Autodesk Fusion 360 part; units mm, degrees
(part 3 of 3)
ref_plane "WorkPlane287" through (0, 27.62, 0) normal (0, 1, 0) x (0, 0, 1)
sketch "Clip release relocated clear of switch" plane through (0, 27.62, 0) normal (0, 1, 0) x (1, 0, 0)
  line L0 (40, -30.3) -> (46, -30.3)
  line L1 (46, -30.3) -> (46, -31.65)
  line L2 (46, -31.65) -> (40, -31.65)
  line L3 (40, -31.65) -> (40, -30.3)
extrude "Clip release relocated clear of switch (1)" cut sketch "Clip release relocated clear of switch" against normal blind 2.1 bodies 1
ref_plane "WorkPlane288" through (0, 0, -4.08) normal (0, 0, 1) x (1, 0, 0)
sketch "Battery landing pad defines assembly bottom datum" plane through (0, 0, -4.08) normal (0, 0, 1) x (1, 0, 0)
  line L0 (-19, -26) -> (-15, -26)
  line L1 (-15, -26) -> (-15, -20)
  line L2 (-15, -20) -> (-19, -20)
  line L3 (-19, -20) -> (-19, -26)
extrude "Battery landing pad defines assembly bottom datum (1)" add sketch "Battery landing pad defines assembly bottom datum" along normal blind 0.95 bodies 1
ref_plane "WorkPlane289" through (0, 0, -4.08) normal (0, 0, 1) x (1, 0, 0)
sketch "Battery landing pad defines assembly bottom datum (1)" plane through (0, 0, -4.08) normal (0, 0, 1) x (1, 0, 0)
  line L0 (-19, 10) -> (-15, 10)
  line L1 (-15, 10) -> (-15, 16)
  line L2 (-15, 16) -> (-19, 16)
  line L3 (-19, 16) -> (-19, 10)
extrude "Battery landing pad defines assembly bottom datum (2)" add sketch "Battery landing pad defines assembly bottom datum (1)" along normal blind 0.95 bodies 1
ref_plane "WorkPlane290" through (0, 0, -4.08) normal (0, 0, 1) x (1, 0, 0)
sketch "Battery landing pad defines assembly bottom datum (2)" plane through (0, 0, -4.08) normal (0, 0, 1) x (1, 0, 0)
  line L0 (9, -26) -> (13, -26)
  line L1 (13, -26) -> (13, -20)
  line L2 (13, -20) -> (9, -20)
  line L3 (9, -20) -> (9, -26)
extrude "Battery landing pad defines assembly bottom datum (3)" add sketch "Battery landing pad defines assembly bottom datum (2)" along normal blind 0.95 bodies 1
ref_plane "WorkPlane291" through (0, 0, -4.08) normal (0, 0, 1) x (1, 0, 0)
sketch "Battery landing pad defines assembly bottom datum (3)" plane through (0, 0, -4.08) normal (0, 0, 1) x (1, 0, 0)
  line L0 (9, 10) -> (13, 10)
  line L1 (13, 10) -> (13, 16)
  line L2 (13, 16) -> (9, 16)
  line L3 (9, 16) -> (9, 10)
extrude "Battery landing pad defines assembly bottom datum (4)" add sketch "Battery landing pad defines assembly bottom datum (3)" along normal blind 0.95 bodies 1
ref_plane "WorkPlane292" through (52.5316, 0, 0) normal (1, 0, 0) x (0, 1, 0)
sketch "USB C 9.4 x 3.4 corner chamfer 0.1 review" plane through (52.5316, 0, 0) normal (1, 0, 0) x (0, 0, -1)
  line L0 (-8.67, -22.84) -> (-8.67, -13.64)
  line L1 (-8.67, -13.64) -> (-8.77, -13.54)
  line L2 (-8.77, -13.54) -> (-11.97, -13.54)
  line L3 (-11.97, -13.54) -> (-12.07, -13.64)
  line L4 (-12.07, -13.64) -> (-12.07, -22.84)
  line L5 (-12.07, -22.84) -> (-11.97, -22.94)
  line L6 (-11.97, -22.94) -> (-8.77, -22.94)
  line L7 (-8.77, -22.94) -> (-8.67, -22.84)
extrude "USB C corner clearance review 2026-10-18" cut sketch "USB C 9.4 x 3.4 corner chamfer 0.1 review" against normal blind 3 bodies 1
ref_plane "WorkPlane293" through (0, 0, 39.1) normal (0, 0, 1) x (1, 0, 0)
sketch "OLED 0.96 external glass opening 19.86 x 27.30" plane through (0, 0, 39.1) normal (0, 0, 1) x (1, 0, 0)
  line L0 (22.07, -19.15) -> (41.93, -19.15)
  line L1 (41.93, -19.15) -> (41.93, 8.15)
  line L2 (41.93, 8.15) -> (22.07, 8.15)
  line L3 (22.07, 8.15) -> (22.07, -19.15)
extrude "OLED 0.96 external glass opening 19.86 x 27.30 (1)" cut sketch "OLED 0.96 external glass opening 19.86 x 27.30" against normal blind 1.6 bodies 2
ref_plane "WorkPlane294" through (0, 0, 34.9) normal (0, 0, 1) x (1, 0, 0)
sketch "REF_DO_NOT_PRINT OLED096 nominal PCB 27 x 27 USER 0.96 variant" plane through (0, 0, 34.9) normal (0, 0, 1) x (1, 0, 0)
  line L0 (18.5, -19) -> (45.5, -19)
  line L1 (45.5, -19) -> (45.5, 8)
  line L2 (45.5, 8) -> (18.5, 8)
  line L3 (18.5, 8) -> (18.5, -19)
extrude "REF_DO_NOT_PRINT OLED096 nominal PCB 27 x 27 USER 0.96 variant (1)" add sketch "REF_DO_NOT_PRINT OLED096 nominal PCB 27 x 27 USER 0.96 variant" along normal blind 1.6 separate body makes body 35
ref_plane "WorkPlane295" through (0, 0, 36.5) normal (0, 0, 1) x (1, 0, 0)
sketch "REF_DO_NOT_PRINT OLED096 external glass 19.26 x 26.7 DATASHEET" plane through (0, 0, 36.5) normal (0, 0, 1) x (1, 0, 0)
  line L0 (22.37, -18.85) -> (41.63, -18.85)
  line L1 (41.63, -18.85) -> (41.63, 7.85)
  line L2 (41.63, 7.85) -> (22.37, 7.85)
  line L3 (22.37, 7.85) -> (22.37, -18.85)
extrude "REF_DO_NOT_PRINT OLED096 external glass 19.26 x 26.7 DATASHEET (1)" add sketch "REF_DO_NOT_PRINT OLED096 external glass 19.26 x 26.7 DATASHEET" along normal blind 2.5 separate body makes body 36
ref_plane "WorkPlane296" through (0, 0, 33.5) normal (0, 0, 1) x (1, 0, 0)
sketch "OLED096_removable_carrier" plane through (0, 0, 33.5) normal (0, 0, 1) x (1, 0, 0)
  line L0 (14.7, -21) -> (49.3, -21)
  line L1 (49.3, -21) -> (49.3, 10)
  line L2 (49.3, 10) -> (14.7, 10)
  line L3 (14.7, 10) -> (14.7, -21)
extrude "OLED096_removable_carrier (1)" add sketch "OLED096_removable_carrier" along normal blind 1.2 separate body makes body 37
ref_plane "WorkPlane297" through (0, 0, 33.4) normal (0, 0, 1) x (1, 0, 0)
sketch "OLED carrier underside service opening 22 x 22" plane through (0, 0, 33.4) normal (0, 0, 1) x (1, 0, 0)
  line L0 (21, -16.5) -> (43, -16.5)
  line L1 (43, -16.5) -> (43, 5.5)
  line L2 (43, 5.5) -> (21, 5.5)
  line L3 (21, 5.5) -> (21, -16.5)
extrude "OLED carrier underside service opening 22 x 22 (1)" cut sketch "OLED carrier underside service opening 22 x 22" along normal blind 1.4 bodies 37
ref_plane "WorkPlane298" through (0, 0, 33) normal (0, 0, 1) x (1, 0, 0)
sketch "OLED carrier flexible holder 0.6 PETG" plane through (0, 0, 33) normal (0, 0, 1) x (1, 0, 0)
  line L0 (14.9, -21.9) -> (18.9, -21.9)
  line L1 (18.9, -21.9) -> (18.9, -21.3)
  line L2 (18.9, -21.3) -> (14.9, -21.3)
  line L3 (14.9, -21.3) -> (14.9, -21.9)
extrude "OLED carrier flexible holder 0.6 PETG (1)" add sketch "OLED carrier flexible holder 0.6 PETG" along normal blind 4.8 bodies 2
ref_plane "WorkPlane299" through (0, 0, 33.1) normal (0, 0, 1) x (1, 0, 0)
sketch "OLED carrier lower capture ledge" plane through (0, 0, 33.1) normal (0, 0, 1) x (1, 0, 0)
  line L0 (14.9, -21.9) -> (18.9, -21.9)
  line L1 (18.9, -21.9) -> (18.9, -20.6)
  line L2 (18.9, -20.6) -> (14.9, -20.6)
  line L3 (14.9, -20.6) -> (14.9, -21.9)
extrude "OLED carrier lower capture ledge (1)" add sketch "OLED carrier lower capture ledge" along normal blind 0.3 bodies 2
ref_plane "WorkPlane300" through (0, 0, 34.8) normal (0, 0, 1) x (1, 0, 0)
sketch "OLED carrier upper stop" plane through (0, 0, 34.8) normal (0, 0, 1) x (1, 0, 0)
  line L0 (16.2, -21) -> (17.6, -21)
  line L1 (17.6, -21) -> (17.6, -20.3)
  line L2 (17.6, -20.3) -> (16.2, -20.3)
  line L3 (16.2, -20.3) -> (16.2, -21)
extrude "OLED carrier upper stop (1)" add sketch "OLED carrier upper stop" along normal blind 3 bodies 2
ref_plane "WorkPlane301" through (0, 0, 33) normal (0, 0, 1) x (1, 0, 0)
sketch "OLED carrier flexible holder 0.6 PETG (1)" plane through (0, 0, 33) normal (0, 0, 1) x (1, 0, 0)
  line L0 (14.9, 10.3) -> (18.9, 10.3)
  line L1 (18.9, 10.3) -> (18.9, 10.9)
  line L2 (18.9, 10.9) -> (14.9, 10.9)
  line L3 (14.9, 10.9) -> (14.9, 10.3)
extrude "OLED carrier flexible holder 0.6 PETG (2)" add sketch "OLED carrier flexible holder 0.6 PETG (1)" along normal blind 4.8 bodies 2
ref_plane "WorkPlane302" through (0, 0, 33.1) normal (0, 0, 1) x (1, 0, 0)
sketch "OLED carrier lower capture ledge (1)" plane through (0, 0, 33.1) normal (0, 0, 1) x (1, 0, 0)
  line L0 (14.9, 9.6) -> (18.9, 9.6)
  line L1 (18.9, 9.6) -> (18.9, 10.9)
  line L2 (18.9, 10.9) -> (14.9, 10.9)
  line L3 (14.9, 10.9) -> (14.9, 9.6)
extrude "OLED carrier lower capture ledge (2)" add sketch "OLED carrier lower capture ledge (1)" along normal blind 0.3 bodies 2
ref_plane "WorkPlane303" through (0, 0, 34.8) normal (0, 0, 1) x (1, 0, 0)
sketch "OLED carrier upper stop (1)" plane through (0, 0, 34.8) normal (0, 0, 1) x (1, 0, 0)
  line L0 (16.2, 9.3) -> (17.6, 9.3)
  line L1 (17.6, 9.3) -> (17.6, 10)
  line L2 (17.6, 10) -> (16.2, 10)
  line L3 (16.2, 10) -> (16.2, 9.3)
extrude "OLED carrier upper stop (2)" add sketch "OLED carrier upper stop (1)" along normal blind 3 bodies 2
ref_plane "WorkPlane304" through (0, 0, 33) normal (0, 0, 1) x (1, 0, 0)
sketch "OLED carrier flexible holder 0.6 PETG (2)" plane through (0, 0, 33) normal (0, 0, 1) x (1, 0, 0)
  line L0 (45.1, -21.9) -> (49.1, -21.9)
  line L1 (49.1, -21.9) -> (49.1, -21.3)
  line L2 (49.1, -21.3) -> (45.1, -21.3)
  line L3 (45.1, -21.3) -> (45.1, -21.9)
extrude "OLED carrier flexible holder 0.6 PETG (3)" add sketch "OLED carrier flexible holder 0.6 PETG (2)" along normal blind 4.8 bodies 2
ref_plane "WorkPlane305" through (0, 0, 33.1) normal (0, 0, 1) x (1, 0, 0)
sketch "OLED carrier lower capture ledge (2)" plane through (0, 0, 33.1) normal (0, 0, 1) x (1, 0, 0)
  line L0 (45.1, -21.9) -> (49.1, -21.9)
  line L1 (49.1, -21.9) -> (49.1, -20.6)
  line L2 (49.1, -20.6) -> (45.1, -20.6)
  line L3 (45.1, -20.6) -> (45.1, -21.9)
extrude "OLED carrier lower capture ledge (3)" add sketch "OLED carrier lower capture ledge (2)" along normal blind 0.3 bodies 2
ref_plane "WorkPlane306" through (0, 0, 34.8) normal (0, 0, 1) x (1, 0, 0)
sketch "OLED carrier upper stop (2)" plane through (0, 0, 34.8) normal (0, 0, 1) x (1, 0, 0)
  line L0 (46.4, -21) -> (47.8, -21)
  line L1 (47.8, -21) -> (47.8, -20.3)
  line L2 (47.8, -20.3) -> (46.4, -20.3)
  line L3 (46.4, -20.3) -> (46.4, -21)
extrude "OLED carrier upper stop (3)" add sketch "OLED carrier upper stop (2)" along normal blind 3 bodies 2
ref_plane "WorkPlane307" through (0, 0, 33) normal (0, 0, 1) x (1, 0, 0)
sketch "OLED carrier flexible holder 0.6 PETG (3)" plane through (0, 0, 33) normal (0, 0, 1) x (1, 0, 0)
  line L0 (45.1, 10.3) -> (49.1, 10.3)
  line L1 (49.1, 10.3) -> (49.1, 10.9)
  line L2 (49.1, 10.9) -> (45.1, 10.9)
  line L3 (45.1, 10.9) -> (45.1, 10.3)
extrude "OLED carrier flexible holder 0.6 PETG (4)" add sketch "OLED carrier flexible holder 0.6 PETG (3)" along normal blind 4.8 bodies 2
ref_plane "WorkPlane308" through (0, 0, 33.1) normal (0, 0, 1) x (1, 0, 0)
sketch "OLED carrier lower capture ledge (3)" plane through (0, 0, 33.1) normal (0, 0, 1) x (1, 0, 0)
  line L0 (45.1, 9.6) -> (49.1, 9.6)
  line L1 (49.1, 9.6) -> (49.1, 10.9)
  line L2 (49.1, 10.9) -> (45.1, 10.9)
  line L3 (45.1, 10.9) -> (45.1, 9.6)
extrude "OLED carrier lower capture ledge (4)" add sketch "OLED carrier lower capture ledge (3)" along normal blind 0.3 bodies 2
ref_plane "WorkPlane309" through (0, 0, 34.8) normal (0, 0, 1) x (1, 0, 0)
sketch "OLED carrier upper stop (3)" plane through (0, 0, 34.8) normal (0, 0, 1) x (1, 0, 0)
  line L0 (46.4, 9.3) -> (47.8, 9.3)
  line L1 (47.8, 9.3) -> (47.8, 10)
  line L2 (47.8, 10) -> (46.4, 10)
  line L3 (46.4, 10) -> (46.4, 9.3)
extrude "OLED carrier upper stop (4)" add sketch "OLED carrier upper stop (3)" along normal blind 3 bodies 2
ref_plane "WorkPlane310" through (0, 0, -2) normal (0, 0, 1) x (1, 0, 0)
sketch "REF_DO_NOT_PRINT MT3608 17 x 36 x 6.5 MANUFACTURER" plane through (0, 0, -2) normal (0, 0, 1) x (1, 0, 0)
  line L0 (18, -22.5) -> (35, -22.5)
  line L1 (35, -22.5) -> (35, 13.5)
  line L2 (35, 13.5) -> (18, 13.5)
  line L3 (18, 13.5) -> (18, -22.5)
extrude "REF_DO_NOT_PRINT MT3608 17 x 36 x 6.5 MANUFACTURER (1)" add sketch "REF_DO_NOT_PRINT MT3608 17 x 36 x 6.5 MANUFACTURER" along normal blind 6.5 separate body makes body 38
ref_plane "WorkPlane311" through (0, 0, -4.08) normal (0, 0, 1) x (1, 0, 0)
sketch "MT3608 edge mounting pad 2 x 2" plane through (0, 0, -4.08) normal (0, 0, 1) x (1, 0, 0)
  line L0 (18, -22.5) -> (20, -22.5)
  line L1 (20, -22.5) -> (20, -20.5)
  line L2 (20, -20.5) -> (18, -20.5)
  line L3 (18, -20.5) -> (18, -22.5)
extrude "MT3608 edge mounting pad 2 x 2 (1)" add sketch "MT3608 edge mounting pad 2 x 2" along normal blind 2.08 bodies 1
ref_plane "WorkPlane312" through (0, 0, -4.08) normal (0, 0, 1) x (1, 0, 0)
sketch "MT3608 edge mounting pad 2 x 2 (1)" plane through (0, 0, -4.08) normal (0, 0, 1) x (1, 0, 0)
  line L0 (18, 11.5) -> (20, 11.5)
  line L1 (20, 11.5) -> (20, 13.5)
  line L2 (20, 13.5) -> (18, 13.5)
  line L3 (18, 13.5) -> (18, 11.5)
extrude "MT3608 edge mounting pad 2 x 2 (2)" add sketch "MT3608 edge mounting pad 2 x 2 (1)" along normal blind 2.08 bodies 1
ref_plane "WorkPlane313" through (0, 0, -4.08) normal (0, 0, 1) x (1, 0, 0)
sketch "MT3608 edge mounting pad 2 x 2 (2)" plane through (0, 0, -4.08) normal (0, 0, 1) x (1, 0, 0)
  line L0 (33, -22.5) -> (35, -22.5)
  line L1 (35, -22.5) -> (35, -20.5)
  line L2 (35, -20.5) -> (33, -20.5)
  line L3 (33, -20.5) -> (33, -22.5)
extrude "MT3608 edge mounting pad 2 x 2 (3)" add sketch "MT3608 edge mounting pad 2 x 2 (2)" along normal blind 2.08 bodies 1
ref_plane "WorkPlane314" through (0, 0, -4.08) normal (0, 0, 1) x (1, 0, 0)
sketch "MT3608 edge mounting pad 2 x 2 (3)" plane through (0, 0, -4.08) normal (0, 0, 1) x (1, 0, 0)
  line L0 (33, 11.5) -> (35, 11.5)
  line L1 (35, 11.5) -> (35, 13.5)
  line L2 (35, 13.5) -> (33, 13.5)
  line L3 (33, 13.5) -> (33, 11.5)
extrude "MT3608 edge mounting pad 2 x 2 (4)" add sketch "MT3608 edge mounting pad 2 x 2 (3)" along normal blind 2.08 bodies 1
ref_plane "WorkPlane315" through (0, 0, -4.08) normal (0, 0, 1) x (1, 0, 0)
sketch "Battery end fence 47 mm inner spacing 103443" plane through (0, 0, -4.08) normal (0, 0, 1) x (1, 0, 0)
  line L0 (-16, -29.1) -> (10, -29.1)
  line L1 (10, -29.1) -> (10, -28.5)
  line L2 (10, -28.5) -> (-16, -28.5)
  line L3 (-16, -28.5) -> (-16, -29.1)
extrude "Battery end fence 47 mm inner spacing 103443 (1)" add sketch "Battery end fence 47 mm inner spacing 103443" along normal blind 3.08 bodies 1
ref_plane "WorkPlane316" through (0, 0, -4.08) normal (0, 0, 1) x (1, 0, 0)
sketch "Battery end fence 47 mm inner spacing 103443 (1)" plane through (0, 0, -4.08) normal (0, 0, 1) x (1, 0, 0)
  line L0 (-16, 18.5) -> (10, 18.5)
  line L1 (10, 18.5) -> (10, 19.1)
  line L2 (10, 19.1) -> (-16, 19.1)
  line L3 (-16, 19.1) -> (-16, 18.5)
extrude "Battery end fence 47 mm inner spacing 103443 (2)" add sketch "Battery end fence 47 mm inner spacing 103443 (1)" along normal blind 3.08 bodies 1
fillet "Fillet2" radius 1 8 edges at (51.1564, -37.1504, 39) (51.8632, -5.24, 39) (51.0136, 26.8131, 39) (13.4316, 27.52, 39) (-24.2931, 26.6704, 39) (-25, -5.24, 39) (-24.1504, -37.2931, 39) (13.4316, -38, 39) on bodies 2
fillet "Fillet3" radius 1 8 edges at (-24.1504, 26.8131, -5.2316) (13.4316, 27.52, -5.2316) (51.1564, 26.6704, -5.2316) (51.8632, -5.24, -5.2316) (51.0136, -37.2931, -5.2316) (13.4316, -38, -5.2316) (-24.2931, -37.1504, -5.2316) (-25, -5.24, -5.2316) on bodies 1
ref_plane "WorkPlane317" through (0, 0, 26) normal (0, 0, 1) x (1, 0, 0)
sketch "REMOVE keypad standoffs and capture shelves" plane through (0, 0, 26) normal (0, 0, 1) x (1, 0, 0)
  line L0 (-14.1, -26.1) -> (14.5, -26.1)
  line L1 (14.5, -26.1) -> (14.5, 9.1)
  line L2 (14.5, 9.1) -> (-14.1, 9.1)
  line L3 (-14.1, 9.1) -> (-14.1, -26.1)
extrude "REMOVE keypad standoffs and capture shelves (1)" cut sketch "REMOVE keypad standoffs and capture shelves" along normal blind 11.8 bodies 2
ref_plane "WorkPlane318" through (0, 0, 26) normal (0, 0, 1) x (1, 0, 0)
sketch "REMOVE OLED standoffs and capture shelves" plane through (0, 0, 26) normal (0, 0, 1) x (1, 0, 0)
  line L0 (14.5, -22.4) -> (49.5, -22.4)
  line L1 (49.5, -22.4) -> (49.5, 11.4)
  line L2 (49.5, 11.4) -> (14.5, 11.4)
  line L3 (14.5, 11.4) -> (14.5, -22.4)
extrude "REMOVE OLED standoffs and capture shelves (1)" cut sketch "REMOVE OLED standoffs and capture shelves" along normal blind 11.8 bodies 2
ref_plane "WorkPlane319" through (0, 0, 30.2) normal (0, 0, 1) x (1, 0, 0)
sketch "CLIP 1 beam thickness 1.6 mm inward reinforcement" plane through (0, 0, 30.2) normal (0, 0, 1) x (1, 0, 0)
  line L0 (-10.6, -36.1) -> (-5.4, -36.1)
  line L1 (-5.4, -36.1) -> (-5.4, -34.5)
  line L2 (-5.4, -34.5) -> (-10.6, -34.5)
  line L3 (-10.6, -34.5) -> (-10.6, -36.1)
extrude "CLIP 1 beam thickness 1.6 mm inward reinforcement (1)" add sketch "CLIP 1 beam thickness 1.6 mm inward reinforcement" along normal blind 7.8 bodies 2
ref_plane "WorkPlane320" through (0, 0, 30.2) normal (0, 0, 1) x (1, 0, 0)
sketch "CLIP 2 beam thickness 1.6 mm inward reinforcement" plane through (0, 0, 30.2) normal (0, 0, 1) x (1, 0, 0)
  line L0 (32.4, -36.1) -> (37.6, -36.1)
  line L1 (37.6, -36.1) -> (37.6, -34.5)
  line L2 (37.6, -34.5) -> (32.4, -34.5)
  line L3 (32.4, -34.5) -> (32.4, -36.1)
extrude "CLIP 2 beam thickness 1.6 mm inward reinforcement (1)" add sketch "CLIP 2 beam thickness 1.6 mm inward reinforcement" along normal blind 7.8 bodies 2
ref_plane "WorkPlane321" through (0, 0, 30.2) normal (0, 0, 1) x (1, 0, 0)
sketch "CLIP 3 beam thickness 1.6 mm inward reinforcement" plane through (0, 0, 30.2) normal (0, 0, 1) x (1, 0, 0)
  line L0 (-10.6, 24.02) -> (-5.4, 24.02)
  line L1 (-5.4, 24.02) -> (-5.4, 25.62)
  line L2 (-5.4, 25.62) -> (-10.6, 25.62)
  line L3 (-10.6, 25.62) -> (-10.6, 24.02)
extrude "CLIP 3 beam thickness 1.6 mm inward reinforcement (1)" add sketch "CLIP 3 beam thickness 1.6 mm inward reinforcement" along normal blind 7.8 bodies 2
ref_plane "WorkPlane322" through (0, 0, 30.2) normal (0, 0, 1) x (1, 0, 0)
sketch "CLIP 4 beam thickness 1.6 mm inward reinforcement" plane through (0, 0, 30.2) normal (0, 0, 1) x (1, 0, 0)
  line L0 (40.4, 24.02) -> (45.6, 24.02)
  line L1 (45.6, 24.02) -> (45.6, 25.62)
  line L2 (45.6, 25.62) -> (40.4, 25.62)
  line L3 (40.4, 25.62) -> (40.4, 24.02)
extrude "CLIP 4 beam thickness 1.6 mm inward reinforcement (1)" add sketch "CLIP 4 beam thickness 1.6 mm inward reinforcement" along normal blind 7.8 bodies 2
hidden bodies 1 3 4 5 6 7 8 9 10 11 12 13 14 15 16 17 18 19 20 21 22 23 24 25 26 27 28 29 30 31 32 33 34 35 36 37 38
equation "d5 = 63 / 57"
equation "d13 = wall"
equation "wall = 1.2 mm" comment "Housing wall"
equation "lid_skin = 1.2 mm" comment "Lid roof"
equation "assembly_height = 40 mm" comment "User confirmed electronics stack height"
equation "switch_length = 13 mm" comment "User supplied switch length"
equation "switch_height = 8.5 mm" comment "User supplied switch height"
equation "clip_clearance = 0.3 mm" comment "PETG initial fit clearance; validate on test coupon"
equation "antenna_hole = 8 mm" comment "PROVISIONAL SMA clearance; verify connector diameter"
equation "pcb_length = 70 mm" comment "PHOTO ESTIMATE; verify physical PCB"
equation "pcb_width = 60 mm" comment "PHOTO ESTIMATE; verify physical PCB"
named bodies: "Housing_PETG_1.2_DRAFT", "LID_PRINT_1p6_NO_SUPPORTS_NO_STANDOFFS", "REF_DO_NOT_PRINT Main PCB ESTIMATED 70x60x1.6", "REF_DO_NOT_PRINT LiPo envelope ESTIMATED 34x44x10.5", "REF_DO_NOT_PRINT SMA connector PHOTO 5 mm protrusion", "REF_DO_NOT_PRINT Switch 13x8.5 USER DIMENSIONS depth estimated", "REF_DO_NOT_PRINT Charger PCB 17.5 wide PHOTO RULER", "REF_DO_NOT_PRINT Type C shell 9 x 3 PHOTO ESTIMATE", "REF_DO_NOT_PRINT ESP32 PCB 28 wide PHOTO RULER", "REF_DO_NOT_PRINT ESP micro USB shell 7.8 x 3 PHOTO ESTIMATE", "REF_DO_NOT_PRINT ESP32 shield envelope PHOTO ESTIMATE", "Button_01_DRAFT", "REF_DO_NOT_PRINT Tact 01 photo estimate", "Button_02_DRAFT", "REF_DO_NOT_PRINT Tact 02 photo estimate", "Button_03_DRAFT", "REF_DO_NOT_PRINT Tact 03 photo estimate", "Button_04_DRAFT", "REF_DO_NOT_PRINT Tact 04 photo estimate", "Button_05_DRAFT", "REF_DO_NOT_PRINT Tact 05 photo estimate", "Button_06_DRAFT", "REF_DO_NOT_PRINT Tact 06 photo estimate", "Button_07_DRAFT", "REF_DO_NOT_PRINT Tact 07 photo estimate", "Button_08_DRAFT", "REF_DO_NOT_PRINT Tact 08 photo estimate", "REF_DO_NOT_PRINT Keypad PCB moved 2.5 mm right PHOTO", "REF_DO_NOT_PRINT Buzzer approx 12 mm USER diameter height10 PHOTO", "REF_DO_NOT_PRINT Radio PCB 45 x 16 PHOTO APPROX", "REF_DO_NOT_PRINT White harness connector PHOTO APPROX", "REF_DO_NOT_PRINT LED 3 mm PHOTO 1", "REF_DO_NOT_PRINT LED 3 mm PHOTO 2", "REF_DO_NOT_PRINT LED 3 mm PHOTO 3", "REF_DO_NOT_PRINT OLED096 nominal PCB 27 x 27 USER 0.96 variant", "REF_DO_NOT_PRINT OLED096 external glass 19.26 x 26.7 DATASHEET", "OLED096_removable_carrier", "REF_DO_NOT_PRINT MT3608 17 x 36 x 6.5 MANUFACTURER"
